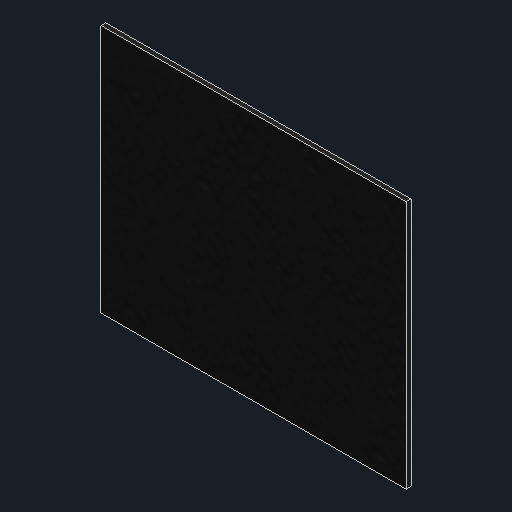
# Autodesk Inventor part: tft_1.8in_glass
Saved by Autodesk Inventor 2027.1 (Build 311270010, 270A)
## iProperties
Created: 2026-10-29
Part Number: tft_1.8in_glass
Material: Generic
Document SubType Name: Modeling
Designer: alexg
Density: 1 g/cm^3
Appearance: Black
Author: alexg
Autodesk Inventor part; units mm, degrees
ref_plane "YZ Plane" through (0, 0, 0) normal (1, 0, 0) x (0, 1, 0)
ref_plane "XZ Plane" through (0, 0, 0) normal (0, 1, 0) x (-1, 0, 0)
ref_plane "Work Plane1" through (0, 0, 27.4) normal (0, 0, 1) x (1, 0, 0)
sketch "Glass sketch" plane through (0, 0, 27.4) normal (0, 0, 1) x (1, 0, 0)
  line L0 (-19, 27) -> (19, 27)
  line L1 (19, 27) -> (19, 58)
  line L2 (19, 58) -> (-19, 58)
  line L3 (-19, 58) -> (-19, 27)
  constraints: 8 end point, 2 parallel, 1 horizontal, 1 perpendicular
extrude "Glass" add sketch "Glass sketch" along normal blind 0.6
body "Solid1"
